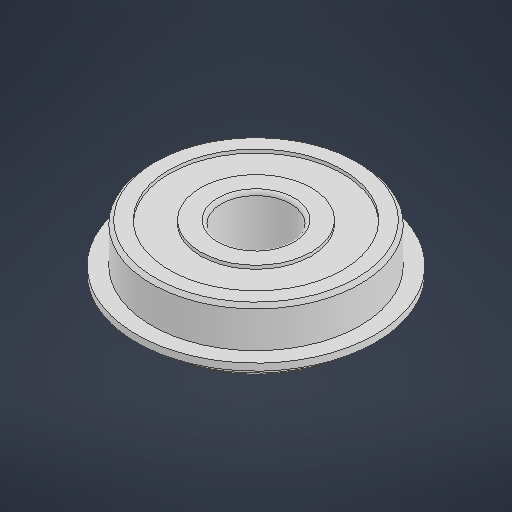
# Autodesk Inventor part: 6200ZZNR
Saved by Autodesk Inventor 2027.1 (Build 311270010, 270A)
## iProperties
Created: 2026-11-11
Part Number: 6200ZZNR
Material: 一般
Document SubType Name: Modeling
Designer: takuya
Density: 1 g/cm^3
Appearance: 既定
Author: takuya
Autodesk Inventor part; units mm, degrees
ref_plane "YZ Plane" through (0, 0, 0) normal (1, 0, 0) x (0, 1, 0)
ref_plane "XZ Plane" through (0, 0, 0) normal (0, 1, 0) x (-1, 0, 0)
sketch "スケッチ1" plane through (0, 0, 0) normal (0, 1, 0) x (-1, 0, 0)
  circle A0 centre (0, 0) radius 15
  dimension "d0" = 30
  constraints: 1 centre point, 1 coincident
  measures "d0" diameter of A0
extrude "押し出し1" add sketch "スケッチ1" along normal blind 9
sketch "スケッチ2" plane through (0, 9, 0) normal (0, 1, 0) x (1, 0, 0)
  circle A0 centre (0, 0) radius 5
  dimension "d3" = 10
  constraints: 1 centre point, 1 coincident
  measures "d3" diameter of A0
extrude "押し出し2" cut sketch "スケッチ2" against normal blind 9
ref_plane "作業平面1" through (0, 3.3, 0) normal (0, 1, 0) x (1, 0, 0)
sketch "スケッチ3" plane through (0, 3.3, 0) normal (0, 1, 0) x (1, 0, 0)
  circle A0 centre (0, 0) radius 17.2
  circle A1 centre (0, 0) radius 5 projected
  circle A2 centre (0, 0) radius 15 projected
  dimension "d7" = 34.4
  constraints: 1 centre point, 1 coincident
  measures "d7" diameter of A0
extrude "押し出し3" add sketch "スケッチ3" against normal blind 1 contours A0
sketch "スケッチ4" plane through (0, 9, 0) normal (0, 1, 0) x (1, 0, 0)
  circle A0 centre (0, 0) radius 5 projected
  circle A1 centre (0, 0) radius 15 projected
  circle A2 centre (0, 0) radius 8
  circle A3 centre (0, 0) radius 12.5
  dimension "d10" = 16
  dimension "d11" = 2.5
  constraints: 2 centre point, 2 coincident
  measures "d10" diameter of A2
  measures "d11" radial gap between concentric circles of A1 A3
extrude "押し出し4" cut sketch "スケッチ4" against normal blind 0.5 contours A3
sketch "スケッチ5" plane through (0, 0, 0) normal (0, -1, 0) x (1, 0, 0)
  circle A0 centre (0, 0) radius 12.5 projected
  circle A1 centre (0, 0) radius 8 projected
extrude "押し出し5" cut sketch "スケッチ5" against normal blind 0.5
chamfer "面取り1" distance 0.5 angle 45 2 edges at (15, 9, 0) (15, 0, 0)
fillet "フィレット1" radius 0.5 2 edges at (-5, 9, 0) (-5, 0, 0)
